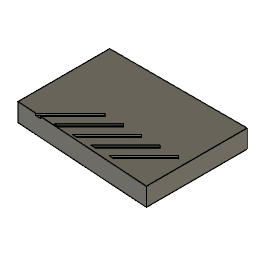
compute_adjust (Autodesk Fusion 360 design; units mm, degrees)
Autodesk Fusion 360 part; units mm, degrees
sketch "Plate" plane through (0, 0, 0) normal (0, 0, 1) x (1, 0, 0)
  line L0 (0, 0) -> (15, -1)
  line L1 (15, -1) -> (15, 10)
  line L2 (15, 10) -> (0, 10)
  line L3 (0, 10) -> (0, 0)
extrude "Extrude1" add sketch "Plate" along normal blind 2
sketch "Groove" plane through (0, 0, 2) normal (0, 0, 1) x (1, 0, 0)
  line L0 (0, 10) -> (0, 0)
  line L1 (0, 0) -> (15, -1)
  line L2 (15, -1) -> (15, 10)
  line L3 (15, 10) -> (0, 10)
  line L4 (0.8586, -1.3586) -> (5.8586, 3.6414)
  line L5 (5.8586, 3.6414) -> (6.1414, 3.3586)
  line L6 (6.1414, 3.3586) -> (1.1414, -1.6414)
  line L7 (1.1414, -1.6414) -> (0.8586, -1.3586)
extrude "Groove cut" cut sketch "Groove" against normal blind 0.2 contours L1 L4 L5 L6
pattern_linear "Groove pattern" count 5 spacing 2 along (1, 0, 0) count 3 spacing 0 along (1, 0, 0) of "Groove cut"
named bodies: "Plate"
